Fan (Autodesk Fusion 360 design; units mm, degrees)
part number: 2026-04-30-00-43-55-192
Autodesk Fusion 360 part; units mm, degrees
sketch "Sketch1" plane through (0, 0, 0) normal (0, 0, 1) x (1, 0, 0)
  line L0 (-20, 25) -> (20, 25)
  line L1 (25, 20) -> (25, -20)
  line L2 (20, -25) -> (-20, -25)
  line L3 (-25, -20) -> (-25, 20)
  line L4 (1.75, 0) -> (22.5, 0)
  line L5 (0, 1.75) -> (0, 22.5)
  circle A0 centre (-20, 20) radius 2.15
  circle A1 centre (-20, -20) radius 2.15
  circle A2 centre (20, -20) radius 2.15
  circle A3 centre (20, 20) radius 2.15
  arc A4 (-20, 25) -> (-25, 20) centre (-20, 20) ccw
  arc A5 (25, 20) -> (20, 25) centre (20, 20) ccw
  arc A6 (20, -25) -> (25, -20) centre (20, -20) ccw
  arc A7 (-25, -20) -> (-20, -25) centre (-20, -20) ccw
  circle A8 centre (0, 0) radius 23.5
  point P0 (-25, 25)
  point P1 (25, 25)
  point P2 (25, -25)
  dimension "d1" = 50
  dimension "d2" = 50
  dimension "d3" = 4.3
  dimension "d4" = 5
  dimension "d5" = 5
  dimension "d6" = 4.3
  dimension "d7" = 5
  dimension "d8" = 4.3
  dimension "d9" = 4.3
  dimension "d10" = 5
  dimension "d15" = 47
  constraint horizontal L0
  constraint vertical L1
  constraint horizontal L2
  constraint vertical L3
  constraint symmetric L0 L2 L4
  constraint symmetric L1 L3 L5
  constraint coincident P0 L0
  constraint coincident P0 L3
  constraint tangent L0 A4
  constraint tangent L3 A4
  constraint coincident P1 L0
  constraint coincident P1 L1
  constraint tangent L0 A5
  constraint tangent L1 A5
  constraint equal A4 A5
  constraint coincident P2 L1
  constraint coincident P2 L2
  constraint tangent L1 A6
  constraint tangent L2 A6
  constraint equal A4 A6
  constraint tangent L2 A7
  constraint tangent L3 A7
  constraint equal A4 A7
  constraint coincident A8.centre origin
  measures "d1" distance of P0 P1
  measures "d2" distance of P1 P2
  measures "d3" diameter of A0
  measures "d4" distance of L0 A0.centre
  measures "d5" distance of L3 A0.centre
  measures "d6" diameter of A1
  measures "d7" distance of L2 A1.centre
  measures "d8" diameter of A2
  measures "d9" diameter of A3
  measures "d10" radius of A4
  measures "d15" diameter of A8
extrude "Extrude1" add sketch "Sketch1" along normal blind 20 contours L0 L1 L2 L3 A4 A5 A6 A7 | A8
extrude "Extrude2" cut sketch "Sketch1" along normal blind 20 contours A8
fillet "Fillet5" radius 1 1 edges at (-21.9097, -8.498, 0)
fillet "Fillet5" radius 1 1 edges at (-21.9097, 8.498, 20)
